veilleuse_dexcom (Autodesk Fusion 360 design; units mm, degrees)
Autodesk Fusion 360 part; units mm, degrees
sketch "Esquisse1" plane through (0, 0, 0) normal (0, 0, 1) x (1, 0, 0)
  circle A0 centre (0, 0) radius 40
extrude "Corps" add sketch "Esquisse1" along normal blind 24 makes body 1
sketch "Esquisse2" plane through (0, 0, 0) normal (0, 0, 1) x (1, 0, 0)
  circle A0 centre (0, 0) radius 37.8
extrude "Levre" add sketch "Esquisse2" along normal blind 6 from surface at 24 bodies 1
sketch "Esquisse3" plane through (0, 0, 0) normal (0, 0, 1) x (1, 0, 0)
  circle A0 centre (0, 0) radius 36
extrude "Cavite" cut sketch "Esquisse3" against normal blind 27.6 from surface at 30 bodies 1
sketch "Esquisse9" plane through (0, 0, 0) normal (0, 0, 1) x (1, 0, 0)
  circle A0 centre (0, 0) radius 40
  circle A1 centre (0, 0) radius 38
extrude "DiffuseurTube" add sketch "Esquisse9" along normal blind 46 from surface at 24 separate body makes body 2
sketch "Esquisse10" plane through (0, 0, 0) normal (0, 0, 1) x (1, 0, 0)
  circle A0 centre (0, 0) radius 40
extrude "DiffuseurChapeau" add sketch "Esquisse10" along normal blind 2 from surface at 70 bodies 2
fillet "CongeChapeau" radius 2 1 edges at (-37.2931, -14.4646, 72) on bodies 2
sketch "Esquisse11" plane through (0, 0, 0) normal (0, 0, 1) x (1, 0, 0)
  circle A0 centre (0, 0) radius 35
  circle A1 centre (0, 0) radius 36
extrude "RenfortLevre" add sketch "Esquisse11" along normal blind 6 from surface at 24 bodies 1
sketch "Esquisse12" plane through (0, 0, 0) normal (0, 1, 0) x (1, 0, 0)
  line L0 (36.6, -25.5) -> (37.9, -25.5)
  line L1 (37.9, -25.5) -> (37.9, -30.5)
  line L2 (37.9, -30.5) -> (36.6, -30.5)
  line L3 (36.6, -30.5) -> (36.6, -25.5)
revolve "BayoEntree" cut sketch "Esquisse12" angle 9 about axis through (0, 0, 1.75) along (0, 0, -1) bodies 1
sketch "Esquisse13" plane through (0, 0, 0) normal (0, 1, 0) x (1, 0, 0)
  line L0 (36.6, -25.5) -> (37.9, -25.5)
  line L1 (37.9, -25.5) -> (37.9, -28)
  line L2 (37.9, -28) -> (36.6, -28)
  line L3 (36.6, -28) -> (36.6, -25.5)
revolve "BayoCanal" cut sketch "Esquisse13" angle 28 about axis through (0, 0, 1.75) along (0, 0, -1) bodies 1
ref_plane "Plan de construction1" through (0, 0, 12.125) normal (0.309017, 0.951057, 0) x (0, 0, 1)
sketch "Esquisse14" plane through (0, 0, 0) normal (0.309017, 0.951057, 0) x (0, 0, 1)
  line L0 (25.5, 36.6) -> (25.5, 36.95)
  line L1 (25.5, 36.95) -> (28, 36.95)
  line L2 (28, 36.95) -> (28, 36.6)
  line L3 (28, 36.6) -> (25.5, 36.6)
revolve "BayoBosse" add sketch "Esquisse14" angle 3 about axis through (0, 0, 1.75) along (0, 0, -1) bodies 1
sketch "Esquisse15" plane through (0, 0, 0) normal (0, 0, 1) x (1, 0, 0)
  line L0 (36.5296, -4.8811) -> (38.2244, -5.0145)
  line L1 (38.2244, -5.0145) -> (38.5382, -1.0268)
  line L2 (38.5382, -1.0268) -> (36.8435, -0.8935)
  line L3 (36.8435, -0.8935) -> (36.5296, -4.8811)
extrude "Ergot" add sketch "Esquisse15" along normal blind 2 from surface at 25.75 bodies 2
pattern_circular "Bayonnette_x3" count 3 over 360 about axis through (0, 0, 1.75) along (0, 0, 1) of "BayoEntree", "BayoCanal", "BayoBosse", "Ergot"
fillet "Congé2" radius 0.7 2 edges at (-28.7155, -23.2534, 26.75) (-27.4592, -24.7244, 26.75) on bodies 1
fillet "Congé3" radius 0.7 4 edges at (34.4958, -13.2417, 26.75) (35.1415, -11.4182, 26.75) (-5.7803, 36.4951, 26.75) (-7.6823, 36.1426, 26.75) on bodies 1
sketch "Esquisse17" plane through (0, 0, 0) normal (0, 0, 1) x (1, 0, 0)
  line L0 (-13.5, 0.35) -> (13.5, 0.35)
  line L1 (13.5, 0.35) -> (13.5, 2.15)
  line L2 (13.5, 2.15) -> (-13.5, 2.15)
  line L3 (-13.5, 2.15) -> (-13.5, 0.35)
extrude "AssiseAntenne (1)" add sketch "Esquisse17" along normal blind 3.4 from surface at 2.4 bodies 1
sketch "Esquisse18" plane through (0, 0, 0) normal (0, 0, 1) x (1, 0, 0)
  line L0 (-13.5, -0.85) -> (13.5, -0.85)
  line L1 (13.5, -0.85) -> (13.5, 0.35)
  line L2 (13.5, 0.35) -> (-13.5, 0.35)
  line L3 (-13.5, 0.35) -> (-13.5, -0.85)
extrude "AssiseAntenneLevre (1)" add sketch "Esquisse18" along normal blind 3.4 from surface at 2.4 bodies 1
sketch "Esquisse19" plane through (0, 0, 0) normal (0, 0, 1) x (1, 0, 0)
  line L0 (11, -34.35) -> (14.55, -34.35)
  line L1 (14.55, -34.35) -> (14.55, -31.75)
  line L2 (14.55, -31.75) -> (11, -31.75)
  line L3 (11, -31.75) -> (11, -34.35)
  line L4 (-14.55, -34.35) -> (-11, -34.35)
  line L5 (-11, -34.35) -> (-11, -31.75)
  line L6 (-11, -31.75) -> (-14.55, -31.75)
  line L7 (-14.55, -31.75) -> (-14.55, -34.35)
extrude "PlotsUSB (1)" add sketch "Esquisse19" along normal blind 3.4 from surface at 2.4 bodies 1
sketch "Esquisse20" plane through (0, 0, 0) normal (0, 0, 1) x (1, 0, 0)
  line L0 (12.85, -34.35) -> (14.55, -34.35)
  line L1 (14.55, -34.35) -> (14.55, 0.35)
  line L2 (14.55, 0.35) -> (12.85, 0.35)
  line L3 (12.85, 0.35) -> (12.85, -34.35)
  line L4 (-14.55, -34.35) -> (-12.85, -34.35)
  line L5 (-12.85, -34.35) -> (-12.85, 0.35)
  line L6 (-12.85, 0.35) -> (-14.55, 0.35)
  line L7 (-14.55, 0.35) -> (-14.55, -34.35)
extrude "GuidesLateraux (1)" add sketch "Esquisse20" along normal blind 6.6 from surface at 2.4 bodies 1
sketch "Esquisse21" plane through (0, 0, 0) normal (0, 0, 1) x (1, 0, 0)
  line L0 (10.8, -34.35) -> (14.55, -34.35)
  line L1 (14.55, -34.35) -> (14.55, -32.55)
  line L2 (14.55, -32.55) -> (10.8, -32.55)
  line L3 (10.8, -32.55) -> (10.8, -34.35)
  line L4 (-14.55, -34.35) -> (-10.8, -34.35)
  line L5 (-10.8, -34.35) -> (-10.8, -32.55)
  line L6 (-10.8, -32.55) -> (-14.55, -32.55)
  line L7 (-14.55, -32.55) -> (-14.55, -34.35)
extrude "LevresUSB (1)" add sketch "Esquisse21" along normal blind 1.95 from surface at 7.05 bodies 1
sketch "Esquisse22" plane through (0, 0, 0) normal (0, 0, 1) x (1, 0, 0)
  line L0 (8.5, 0.35) -> (12.5, 0.35)
  line L1 (12.5, 0.35) -> (12.5, 1.55)
  line L2 (12.5, 1.55) -> (8.5, 1.55)
  line L3 (8.5, 1.55) -> (8.5, 0.35)
  line L4 (-12.5, 0.35) -> (-8.5, 0.35)
  line L5 (-8.5, 0.35) -> (-8.5, 1.55)
  line L6 (-8.5, 1.55) -> (-12.5, 1.55)
  line L7 (-12.5, 1.55) -> (-12.5, 0.35)
extrude "ClipsDoigts (1)" add sketch "Esquisse22" along normal blind 5.9 from surface at 2.4 bodies 1
sketch "Esquisse23" plane through (0, 0, 0) normal (0, 0, 1) x (1, 0, 0)
  line L0 (8.5, -0.45) -> (12.5, -0.45)
  line L1 (12.5, -0.45) -> (12.5, 0.65)
  line L2 (12.5, 0.65) -> (8.5, 0.65)
  line L3 (8.5, 0.65) -> (8.5, -0.45)
  line L4 (-12.5, -0.45) -> (-8.5, -0.45)
  line L5 (-8.5, -0.45) -> (-8.5, 0.65)
  line L6 (-8.5, 0.65) -> (-12.5, 0.65)
  line L7 (-12.5, 0.65) -> (-12.5, -0.45)
extrude "ClipsBecs (1)" add sketch "Esquisse23" along normal blind 1.25 from surface at 7.05 bodies 1
sketch "Esquisse24" plane through (0, 0, 0) normal (0, 0, 1) x (1, 0, 0)
  line L0 (-8.6, -42) -> (8.6, -42)
  line L1 (8.6, -42) -> (8.6, -33)
  line L2 (8.6, -33) -> (-8.6, -33)
  line L3 (-8.6, -33) -> (-8.6, -42)
extrude "FenteUSB2 (1)" cut sketch "Esquisse24" along normal blind 7.1 from surface at 2.4 bodies 1
chamfer "ChanfreinBecs" distance 0.6 angle 45 2 edges at (-10.5, -0.45, 7.05) (10.5, -0.45, 7.05) tangent chain off on bodies 1
ref_plane "Plan de construction2" through (0, -20.9039, 2.4) normal (0, 0, 1) x (1, 0, 0)
sketch "Esquisse25" plane through (0, 0, 2.4) normal (0, 0, 1) x (1, 0, 0)
  circle A0 centre (0, 0) radius 40
  line L0 (-8.6594, -34.9712) -> (8.5521, -34.9712)
  constraint horizontal L0
extrude "Extrusion22" cut sketch "Esquisse24" against normal blind 3 from surface at 4 bodies 1
sketch "Esquisse26" plane through (0, 0, 0) normal (0, 0, 1) x (1, 0, 0)
  circle A0 centre (0, 0) radius 39
extrude "AmincissementDiffuseur" cut sketch "Esquisse26" along normal blind 38.8 from surface at 32 bodies 2
chamfer "ChanfreinRedan" distance 0.8 angle 45 1 edges at (-36.3608, -14.103, 32) tangent chain off on bodies 2
sketch "Esquisse27" plane through (0, 0, 0) normal (0, 0, 1) x (1, 0, 0)
  circle A0 centre (0, 0) radius 37
extrude "ChapeauFin" cut sketch "Esquisse27" along normal blind 0.8 from surface at 70.8 bodies 2
hidden bodies 1
named bodies: "Base", "Diffuseur"
